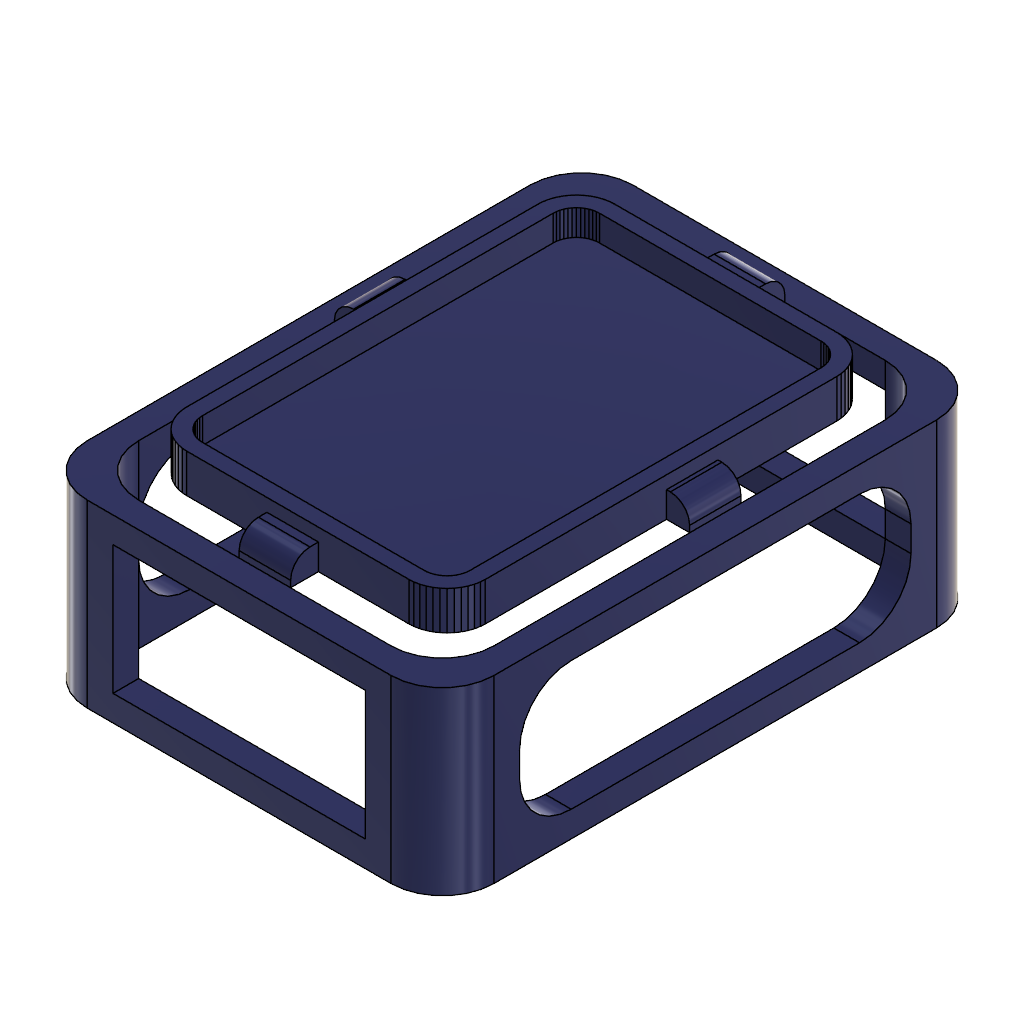
Edubot (Autodesk Fusion 360 archive; units mm, degrees)
design "Estructura"
part number: 2026-10-22-13-33-41-697
Autodesk Fusion 360 part; units mm, degrees
sketch "Boceto1" plane through (0, 0, 0) normal (0, 0, 1) x (1, 0, 0)
  line L0 (13.1802, -732.82) -> (17.6057, -736.701)
  line L1 (17.6057, -736.701) -> (22.5, -739.971)
  line L2 (1.5334, -712.647) -> (3.4254, -718.221)
  line L3 (6.0289, -723.5) -> (9.2992, -728.394)
  line L4 (0.385, -706.874) -> (1.5334, -712.647)
  line L5 (22.5, -739.971) -> (27.7792, -742.574)
  line L6 (9.2992, -728.394) -> (13.1802, -732.82)
  line L7 (33.3531, -744.467) -> (39.1263, -745.615)
  line L8 (0, -701) -> (0.385, -706.874)
  line L9 (39.1263, -745.615) -> (45, -746)
  line L10 (3.4254, -718.221) -> (6.0289, -723.5)
  line L11 (27.7792, -742.574) -> (33.3531, -744.467)
  line L12 (513.971, -723.5) -> (516.575, -718.221)
  line L13 (502.394, -736.701) -> (506.82, -732.82)
  line L14 (510.701, -728.394) -> (513.971, -723.5)
  line L15 (480.874, -745.615) -> (486.647, -744.467)
  line L16 (497.5, -739.971) -> (502.394, -736.701)
  line L17 (492.221, -742.574) -> (497.5, -739.971)
  line L18 (506.82, -732.82) -> (510.701, -728.394)
  line L19 (518.467, -712.647) -> (519.615, -706.874)
  line L20 (486.647, -744.467) -> (492.221, -742.574)
  line L21 (519.615, -706.874) -> (520, -701)
  line L22 (475, -746) -> (480.874, -745.615)
  line L23 (516.575, -718.221) -> (518.467, -712.647)
  line L24 (518.467, -8.3531) -> (516.575, -2.7792)
  line L25 (1.5334, -8.3531) -> (0.385, -14.1263)
  line L26 (9.2992, 7.3943) -> (6.0289, 2.5)
  line L27 (520, -20) -> (519.615, -14.1263)
  line L28 (513.971, 2.5) -> (510.701, 7.3943)
  line L29 (45, 25) -> (39.1263, 24.615)
  line L30 (492.221, 21.5746) -> (486.647, 23.4666)
  line L31 (510.701, 7.3943) -> (506.82, 11.8198)
  line L32 (13.1802, 11.8198) -> (9.2992, 7.3943)
  line L33 (502.394, 15.7008) -> (497.5, 18.9711)
  line L34 (33.3531, 23.4666) -> (27.7792, 21.5746)
  line L35 (497.5, 18.9711) -> (492.221, 21.5746)
  line L36 (6.0289, 2.5) -> (3.4254, -2.7792)
  line L37 (475, 25) -> (45, 25)
  line L38 (0.385, -14.1263) -> (0, -20)
  line L39 (27.7792, 21.5746) -> (22.5, 18.9711)
  line L40 (17.6057, 15.7008) -> (13.1802, 11.8198)
  line L41 (486.647, 23.4666) -> (480.874, 24.615)
  line L42 (39.1263, 24.615) -> (33.3531, 23.4666)
  line L43 (3.4254, -2.7792) -> (1.5334, -8.3531)
  line L44 (519.615, -14.1263) -> (518.467, -8.3531)
  line L45 (516.575, -2.7792) -> (513.971, 2.5)
  line L46 (506.82, 11.8198) -> (502.394, 15.7008)
  line L47 (480.874, 24.615) -> (475, 25)
  line L48 (0, -20) -> (0, -701)
  line L49 (520, -701) -> (520, -20)
  line L50 (22.5, 18.9711) -> (17.6057, 15.7008)
  line L51 (45, -746) -> (475, -746)
  line L52 (-29.4222, -710.7984) -> (-27.5065, -720.4282)
  line L53 (-27.5065, -720.4282) -> (-24.3504, -729.7263)
  line L54 (-24.3504, -729.7263) -> (-20.0072, -738.5329)
  line L55 (-20.0072, -738.5329) -> (-14.5527, -746.6956)
  line L56 (-14.5527, -746.6956) -> (-8.0791, -754.0782)
  line L57 (-8.0791, -754.0782) -> (-0.6958, -760.553)
  line L58 (-0.6958, -760.553) -> (7.469, -766.0083)
  line L59 (7.469, -766.0083) -> (16.273, -770.3492)
  line L60 (16.273, -770.3492) -> (25.5705, -773.5068)
  line L61 (25.5705, -773.5068) -> (35.203, -775.4222)
  line L62 (35.203, -775.4222) -> (44.0179, -776)
  line L63 (44.0179, -776) -> (475.982, -776)
  line L64 (475.982, -776) -> (484.7973, -775.4222)
  line L65 (484.7973, -775.4222) -> (494.4296, -773.5068)
  line L66 (494.4296, -773.5068) -> (503.7274, -770.3491)
  line L67 (503.7274, -770.3491) -> (512.5315, -766.0079)
  line L68 (512.5315, -766.0079) -> (520.6952, -760.5532)
  line L69 (520.6952, -760.5532) -> (528.0788, -754.0788)
  line L70 (528.0788, -754.0788) -> (534.5533, -746.6951)
  line L71 (534.5533, -746.6951) -> (540.0067, -738.5334)
  line L72 (540.0067, -738.5334) -> (544.3505, -729.7274)
  line L73 (544.3505, -729.7274) -> (547.5073, -720.4272)
  line L74 (547.5073, -720.4272) -> (549.4222, -710.7974)
  line L75 (549.4222, -710.7974) -> (550, -701.9821)
  line L76 (550, -701.9821) -> (550, -19.0178)
  line L77 (550, -19.0178) -> (549.4222, -10.2029)
  line L78 (549.4222, -10.2029) -> (547.5073, -0.573)
  line L79 (547.5073, -0.573) -> (544.3505, 8.727)
  line L80 (544.3505, 8.727) -> (540.007, 17.5329)
  line L81 (540.007, 17.5329) -> (534.5531, 25.6957)
  line L82 (534.5531, 25.6957) -> (528.0782, 33.0791)
  line L83 (528.0782, 33.0791) -> (520.6956, 39.5527)
  line L84 (520.6956, 39.5527) -> (512.533, 45.0072)
  line L85 (512.533, 45.0072) -> (503.7263, 49.3504)
  line L86 (503.7263, 49.3504) -> (494.4281, 52.5065)
  line L87 (494.4281, 52.5065) -> (484.7984, 54.4222)
  line L88 (484.7984, 54.4222) -> (475.9821, 55)
  line L89 (475.9821, 55) -> (44.0179, 55)
  line L90 (44.0179, 55) -> (35.202, 54.4221)
  line L91 (35.202, 54.4221) -> (25.572, 52.5066)
  line L92 (25.572, 52.5066) -> (16.2741, 49.3505)
  line L93 (16.2741, 49.3505) -> (7.4676, 45.0075)
  line L94 (7.4676, 45.0075) -> (-0.6962, 39.5525)
  line L95 (-0.6962, 39.5525) -> (-8.0785, 33.0785)
  line L96 (-8.0785, 33.0785) -> (-14.5525, 25.6962)
  line L97 (-14.5525, 25.6962) -> (-20.0075, 17.5324)
  line L98 (-20.0075, 17.5324) -> (-24.3505, 8.7259)
  line L99 (-24.3505, 8.7259) -> (-27.5066, -0.572)
  line L100 (-27.5066, -0.572) -> (-29.4221, -10.202)
  line L101 (-29.4221, -10.202) -> (-30, -19.0179)
  line L102 (-30, -19.0179) -> (-30, -701.9821)
  line L103 (-30, -701.9821) -> (-29.4222, -710.7984)
  dimension "d1" = 30
extrude "Extruir1" add sketch "Boceto1" along normal blind 75 makes body 1
extrude "Extruir2" add sketch "Boceto1" along normal blind 25 contours L0 L1 L2 L3 L4 L5 L6 L7 L8 L9 L10 L11 L12 L13 L14 L15 L16 L17 L18 L19 L20 L21 L22 L23 L24 L25 L26 L27 L28 L29 L30 L31 L32 L33 L34 L35 L36 L37 L38 L39 L40 L41 L42 L43 L44 L45 L46 L47 L48 L49 L50 L51 bodies 1
sketch "Boceto2" plane through (0, 0, 0) normal (0, 0, 1) x (1, 0, 0)
  line L0 (250, -350) -> (250, -850)
  line L1 (494.9533, 129.9503) -> (5.0467, 129.9503)
  line L2 (-94.9533, 29.9503) -> (-94.9533, -729.9503)
  line L3 (5.0467, -829.9503) -> (494.9533, -829.9503)
  line L4 (594.9533, -729.9503) -> (594.9533, 29.9503)
  line L5 (594.9533, 129.9503) -> (-94.9533, -829.9503) construction
  line L6 (-94.9533, 129.9503) -> (594.9533, -829.9503) construction
  line L7 (544.9533, 179.9503) -> (-44.9533, 179.9503)
  line L8 (-144.9533, 79.9503) -> (-144.9533, -779.9503)
  line L9 (-44.9533, -879.9503) -> (544.9533, -879.9503)
  line L10 (644.9533, -779.9503) -> (644.9533, 79.9503)
  arc A0 (-144.9533, -779.9503) -> (-44.9533, -879.9503) centre (-44.9533, -779.9503) ccw
  arc A1 (544.9533, -879.9503) -> (644.9533, -779.9503) centre (544.9533, -779.9503) ccw
  arc A2 (644.9533, 79.9503) -> (544.9533, 179.9503) centre (544.9533, 79.9503) ccw
  arc A3 (-44.9533, 179.9503) -> (-144.9533, 79.9503) centre (-44.9533, 79.9503) ccw
  arc A4 (594.9533, 29.9503) -> (494.9533, 129.9503) centre (494.9533, 29.9503) ccw
  arc A5 (494.9533, -829.9503) -> (594.9533, -729.9503) centre (494.9533, -729.9503) ccw
  arc A6 (-94.9533, -729.9503) -> (5.0467, -829.9503) centre (5.0467, -729.9503) ccw
  line L11 (-94.9533, -300) -> (-94.9533, -250)
  line L12 (-94.9533, -250) -> (-25, -250)
  line L13 (-25, -250) -> (-25, -350)
  line L14 (-25, -350) -> (-94.9533, -350)
  line L15 (550, -300) -> (550, -250)
  line L16 (550, -250) -> (594.9533, -250)
  line L17 (550, -300) -> (550, -350)
  line L18 (550, -350) -> (594.9533, -350)
  line L19 (594.9533, -250) -> (594.9533, -350)
  line L20 (250, -829.9503) -> (300, -829.9503)
  line L21 (300, -829.9503) -> (300, -775)
  line L22 (300, -775) -> (200, -775)
  line L23 (200, -775) -> (200, -829.9503)
  line L24 (250, -829.9503) -> (200, -829.9503)
  line L25 (250, 50) -> (300, 50)
  line L26 (300, 50) -> (300, 129.9503)
  line L27 (300, 129.9503) -> (200, 129.9503)
  line L28 (200, 129.9503) -> (200, 50)
  line L29 (200, 50) -> (300, 50)
  arc A7 (5.0467, 129.9503) -> (-94.9533, 29.9503) centre (5.0467, 29.9503) ccw
  point P0 (250, -350)
  dimension "d7" = 50
  dimension "d8" = 50
  dimension "d9" = 50
  dimension "d10" = 50
  dimension "d11" = 100
  dimension "d33" = 100
  constraint vertical L0
  constraint horizontal L1
  constraint perpendicular L1 L2
  constraint parallel L1 L3
  constraint parallel L2 L4
  constraint coincident L5 P0
  constraint coincident L6 P0
  constraint coincident P0 L0.start
  constraint tangent L8 A0
  constraint tangent L9 A0
  constraint tangent L10 A1
  constraint tangent L9 A1
  constraint equal A0 A1
  constraint tangent L10 A2
  constraint tangent L7 A2
  constraint equal A0 A2
  constraint tangent L7 A3
  constraint tangent L8 A3
  constraint equal A0 A3
  constraint coincident L5.start L1
  constraint coincident L5.start L4
  constraint tangent L1 A4
  constraint tangent L4 A4
  constraint equal A0 A4
  constraint coincident L6.end L3
  constraint coincident L6.end L4
  constraint tangent L3 A5
  constraint tangent L4 A5
  constraint equal A0 A5
  constraint coincident L5.end L2
  constraint coincident L5.end L3
  constraint tangent L2 A6
  constraint tangent L3 A6
  constraint equal A0 A6
  constraint coincident L2 L11.end
  constraint perpendicular L11 L12
  constraint perpendicular L12 L13
  constraint coincident L2 L14.end
  constraint perpendicular L2 L14
  constraint perpendicular L14 L15
  constraint coincident L4 L16.end
  constraint perpendicular L4 L16
  constraint perpendicular L16 L17
  constraint midpoint L4 L18.end
  constraint perpendicular L4 L18
  constraint midpoint L3 L20.start
  constraint coincident L3 L20.end
  constraint perpendicular L20 L21
  constraint perpendicular L21 L22
  constraint coincident L3 L23.end
  constraint perpendicular L3 L23
  constraint perpendicular L0 L25
  constraint coincident L1 L26.end
  constraint perpendicular L1 L26
  constraint perpendicular L27 L28
  constraint perpendicular L26 L29
  constraint coincident L1 L27.end
  constraint coincident L2 L11.start
  constraint coincident L6.start L1
  constraint coincident L6.start L2
  constraint tangent L1 A7
  constraint tangent L2 A7
  measures "d7" distance of L1 L7
  measures "d8" distance of L2 L8
  measures "d9" distance of L3 L9
  measures "d10" distance of L4 L10
  measures "d11" radius of A0
  measures "d33" radius of A7
extrude "Extruir3" add sketch "Boceto2" against normal blind 350 separate body makes body 2
extrude "Extruir4" add sketch "Boceto2" along normal blind 50 contours L2 L11 L12 L13 L14 | L4 L15 L16 L17 L18 L19 bodies 1 2
fillet "Empalme1" radius 37.5 2 edges at (-94.9533, -300, 50) (594.9533, -300, 50) on bodies 1
sketch "Boceto3" plane through (644.9533, 0, 0) normal (1, 0, 0) x (0, 1, 0)
  line L0 (79.9503, 0) -> (-779.9503, 0)
  line L1 (-779.9503, 0) -> (-779.9503, -350)
  line L2 (-779.9503, -350) -> (79.9503, -350)
  line L3 (79.9503, -350) -> (79.9503, 0)
  line L4 (-629.9503, -300) -> (-70.0497, -300)
  line L5 (29.9503, -200) -> (29.9503, -150)
  line L6 (-70.0497, -50) -> (-629.9503, -50)
  line L7 (-729.9503, -150) -> (-729.9503, -200)
  arc A0 (-629.9503, -50) -> (-729.9503, -150) centre (-629.9503, -150) ccw
  arc A1 (-729.9503, -200) -> (-629.9503, -300) centre (-629.9503, -200) ccw
  arc A2 (29.9503, -150) -> (-70.0497, -50) centre (-70.0497, -150) ccw
  arc A3 (-70.0497, -300) -> (29.9503, -200) centre (-70.0497, -200) ccw
  dimension "d19" = 50
  dimension "d20" = 50
  dimension "d21" = 50
  dimension "d22" = 50
  dimension "d23" = 100
  constraint tangent L6 A0
  constraint tangent L7 A0
  constraint tangent L4 A1
  constraint tangent L7 A1
  constraint equal A0 A1
  constraint tangent L6 A2
  constraint tangent L5 A2
  constraint equal A0 A2
  constraint tangent L4 A3
  constraint tangent L5 A3
  constraint equal A0 A3
  measures "d19" distance of L2 L4
  measures "d20" distance of L3 L5
  measures "d21" distance of L0 L6
  measures "d22" distance of L1 L7
  measures "d23" radius of A0
extrude "Extruir5" cut sketch "Boceto3" against normal blind 1900 contours L4 L5 L6 L7 A0 A1 A2 A3 bodies 1
sketch "Boceto4" plane through (0, 179.9503, 0) normal (0, 1, 0) x (-1, 0, 0)
  line L0 (44.9533, 0) -> (-544.9533, 0)
  line L1 (-544.9533, 0) -> (-544.9533, -350)
  line L2 (-544.9533, -350) -> (44.9533, -350)
  line L3 (44.9533, -350) -> (44.9533, 0)
  line L4 (-494.9533, -300) -> (-5.0467, -300)
  line L5 (-5.0467, -300) -> (-5.0467, -50)
  line L6 (-5.0467, -50) -> (-494.9533, -50)
  line L7 (-494.9533, -50) -> (-494.9533, -300)
  dimension "d26" = -50
extrude "Extruir6" cut sketch "Boceto4" against normal blind 1650 contours L4 L5 L6 L7 bodies 1
extrude "Extruir7" add sketch "Boceto2" along normal blind 50 contours L0 L3 L20 L21 L22 | L0 L3 L22 L23 L24 | L1 L25 L26 L27 L28 L29 bodies 1
fillet "Empalme2" radius 37.5 2 edges at (250, -829.9503, 50) (250, 129.9503, 50) on bodies 1
